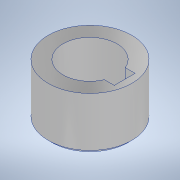
# Autodesk Inventor part: 1.1_4_Spacer
Saved by Autodesk Inventor 2021 (Build 250183000, 183)
## iProperties
Created: 2025-11-21
Part Number: 1.1_4_Spacer
Material: Aluminum 6061
Document SubType Name: Modeling
Designer: Admin
Density: 2.7 g/cm^3
Appearance: Aluminum - Flat
Author: Admin
Autodesk Inventor part; units mm, degrees
ref_plane "YZ Plane" through (0, 0, 0) normal (1, 0, 0) x (0, 1, 0)
ref_plane "XZ Plane" through (0, 0, 0) normal (0, 1, 0) x (-1, 0, 0)
ref_plane "XY Plane" through (0, 0, 0) normal (0, 0, 1) x (1, 0, 0)
sketch "Sketch1" plane through (0, 0, 0) normal (0, 1, 0) x (-1, 0, 0)
  circle A0 centre (0, 0) radius 11
  circle A1 centre (0, 0) radius 7.1
  line L0 (-9.1458, -2.75) -> (-6.5458, -2.75)
  line L1 (-6.5458, -2.75) -> (-6.5458, 2.75)
  line L2 (-6.5458, 2.75) -> (-9.1458, 2.75)
  line L3 (-9.1458, 2.75) -> (-9.1458, -2.75)
  line L4 (-9.1458, -2.75) -> (-6.5458, 2.75) construction
  line L5 (-6.5458, -2.75) -> (-9.1458, 2.75) construction
  point P0 (-7.8458, 0)
  dimension "d1" = 14.2
  dimension "d0" = 22
  dimension "d13" = 2.6
  dimension "d14" = 5.5
  dimension "d15" = 0
  constraints: 12 end point, 2 coincident, 2 midpoint, 2 parallel, 1 centre point, 1 horizontal, 1 perpendicular, 3 other
  measures "d0" diameter of A0
  measures "d13" distance from line of L3 L1.end
  measures "d14" distance of L2.end L0.start
  measures "d15" vertical distance of point (-7.846, 0) point (0, 0)
extrude "Extrusion1" add sketch "Sketch1" along normal blind 14
chamfer "Chamfer3" distance 1 angle 45 1 edges at (11, 0, 0)
body "Solid1"
